211201_P01_WALL-PANEL-FRAME-BACK-LOWER-B1_CAD (Autodesk Fusion 360 design; units mm, degrees)
part number: 2026-11-01-01-29-27-664
description: WALL - PANEL FRAME - BACK LOWER - B1 | Vách hậu - khung dưới trái | P01
part number: 211201
Autodesk Fusion 360 part; units mm, degrees
ref_plane "WorkPlane1" through (0, 0, 112.26) normal (0, 0, 1) x (1, 0, 0) in component "211201 WALL - PANEL FRAME - BACK LOWER - B1"
sketch "SKETCH - RAIL - BOTTOM TUBE" plane through (0, 0, 112.26) normal (0, 0, 1) x (1, 0, 0) in component "211201 WALL - PANEL FRAME - BACK LOWER - B1"
  line L0 (-1201.74, 804) -> (-2.75, 804)
  line L1 (-2.75, 804) -> (-2.75, 844)
  line L2 (-2.75, 844) -> (-1201.74, 844)
  line L3 (-1201.74, 844) -> (-1201.74, 804)
  dimension "d507" = 1198.99
  dimension "d508" = 40
  dimension "d509" = 1201.74
  dimension "d510" = 804
  constraint horizontal L0
  constraint vertical L1
  constraint horizontal L2
  constraint vertical L3
  measures "d507" horizontal distance of L0.start L0.end
  measures "d508" vertical distance of L0.start L2.end
  measures "d509" horizontal distance of origin L0.start
  measures "d510" vertical distance of origin L0.start
extrude "EXTRUDE - RAIL - BOTTOM TUBE" add sketch "SKETCH - RAIL - BOTTOM TUBE" along normal blind 20 makes body 1 in component "211201 WALL - PANEL FRAME - BACK LOWER - B1"
ref_plane "WorkPlane2" through (0, 0, 113.46) normal (0, 0, 1) x (1, 0, 0) in component "211201 WALL - PANEL FRAME - BACK LOWER - B1"
sketch "SKETCH - RAIL - BOTTOM BORE" plane through (0, 0, 113.46) normal (0, 0, 1) x (1, 0, 0) in component "211201 WALL - PANEL FRAME - BACK LOWER - B1"
  line L0 (-1201.74, 805.2) -> (-2.75, 805.2)
  line L1 (-2.75, 805.2) -> (-2.75, 842.8)
  line L2 (-2.75, 842.8) -> (-1201.74, 842.8)
  line L3 (-1201.74, 842.8) -> (-1201.74, 805.2)
  dimension "d515" = 1198.99
  dimension "d516" = 37.6
  dimension "d517" = 1201.74
  dimension "d518" = 805.2
  constraint horizontal L0
  constraint vertical L1
  constraint horizontal L2
  constraint vertical L3
  measures "d515" horizontal distance of L0.start L0.end
  measures "d516" vertical distance of L0.start L2.end
  measures "d517" horizontal distance of origin L0.start
  measures "d518" vertical distance of origin L0.start
extrude "CUT - RAIL - BOTTOM BORE" cut sketch "SKETCH - RAIL - BOTTOM BORE" along normal blind 17.6 bodies 1 in component "211201 WALL - PANEL FRAME - BACK LOWER - B1"
ref_plane "WorkPlane3" through (0, 0, 1210.87) normal (0, 0, 1) x (1, 0, 0) in component "211201 WALL - PANEL FRAME - BACK LOWER - B1"
sketch "SKETCH - RAIL - TOP TUBE" plane through (0, 0, 1210.87) normal (0, 0, 1) x (1, 0, 0) in component "211201 WALL - PANEL FRAME - BACK LOWER - B1"
  line L0 (-1201.74, 804) -> (-2.75, 804)
  line L1 (-2.75, 804) -> (-2.75, 844)
  line L2 (-2.75, 844) -> (-1201.74, 844)
  line L3 (-1201.74, 844) -> (-1201.74, 804)
  dimension "d523" = 1198.99
  dimension "d524" = 40
  dimension "d525" = 1201.74
  dimension "d526" = 804
  constraint horizontal L0
  constraint vertical L1
  constraint horizontal L2
  constraint vertical L3
  measures "d523" horizontal distance of L0.start L0.end
  measures "d524" vertical distance of L0.start L2.end
  measures "d525" horizontal distance of origin L0.start
  measures "d526" vertical distance of origin L0.start
extrude "EXTRUDE - RAIL - TOP TUBE" add sketch "SKETCH - RAIL - TOP TUBE" along normal blind 20 separate body makes body 2 in component "211201 WALL - PANEL FRAME - BACK LOWER - B1"
ref_plane "WorkPlane4" through (0, 0, 1212.07) normal (0, 0, 1) x (1, 0, 0) in component "211201 WALL - PANEL FRAME - BACK LOWER - B1"
sketch "SKETCH - RAIL - TOP BORE" plane through (0, 0, 1212.07) normal (0, 0, 1) x (1, 0, 0) in component "211201 WALL - PANEL FRAME - BACK LOWER - B1"
  line L0 (-1201.74, 805.2) -> (-2.75, 805.2)
  line L1 (-2.75, 805.2) -> (-2.75, 842.8)
  line L2 (-2.75, 842.8) -> (-1201.74, 842.8)
  line L3 (-1201.74, 842.8) -> (-1201.74, 805.2)
  dimension "d531" = 1198.99
  dimension "d532" = 37.6
  dimension "d533" = 1201.74
  dimension "d534" = 805.2
  constraint horizontal L0
  constraint vertical L1
  constraint horizontal L2
  constraint vertical L3
  measures "d531" horizontal distance of L0.start L0.end
  measures "d532" vertical distance of L0.start L2.end
  measures "d533" horizontal distance of origin L0.start
  measures "d534" vertical distance of origin L0.start
extrude "CUT - RAIL - TOP BORE" cut sketch "SKETCH - RAIL - TOP BORE" along normal blind 17.6 bodies 2 in component "211201 WALL - PANEL FRAME - BACK LOWER - B1"
ref_plane "WorkPlane5" through (0, 0, 132.26) normal (0, 0, 1) x (1, 0, 0) in component "211201 WALL - PANEL FRAME - BACK LOWER - B1"
sketch "SKETCH - STILE - OUTER TUBE" plane through (0, 0, 132.26) normal (0, 0, 1) x (1, 0, 0) in component "211201 WALL - PANEL FRAME - BACK LOWER - B1"
  line L0 (-1201.74, 804) -> (-1181.74, 804)
  line L1 (-1181.74, 804) -> (-1181.74, 844)
  line L2 (-1181.74, 844) -> (-1201.74, 844)
  line L3 (-1201.74, 844) -> (-1201.74, 804)
  dimension "d539" = 20
  dimension "d540" = 40
  dimension "d541" = 1201.74
  dimension "d542" = 804
  constraint horizontal L0
  constraint vertical L1
  constraint horizontal L2
  constraint vertical L3
  measures "d539" horizontal distance of L0.start L0.end
  measures "d540" vertical distance of L0.start L2.end
  measures "d541" horizontal distance of origin L0.start
  measures "d542" vertical distance of origin L0.start
extrude "EXTRUDE - STILE - OUTER TUBE" add sketch "SKETCH - STILE - OUTER TUBE" along normal blind 1078.61 separate body makes body 3 in component "211201 WALL - PANEL FRAME - BACK LOWER - B1"
ref_plane "WorkPlane6" through (0, 0, 132.26) normal (0, 0, 1) x (1, 0, 0) in component "211201 WALL - PANEL FRAME - BACK LOWER - B1"
sketch "SKETCH - STILE - OUTER BORE" plane through (0, 0, 132.26) normal (0, 0, 1) x (1, 0, 0) in component "211201 WALL - PANEL FRAME - BACK LOWER - B1"
  line L0 (-1200.54, 805.2) -> (-1182.94, 805.2)
  line L1 (-1182.94, 805.2) -> (-1182.94, 842.8)
  line L2 (-1182.94, 842.8) -> (-1200.54, 842.8)
  line L3 (-1200.54, 842.8) -> (-1200.54, 805.2)
  dimension "d547" = 17.6
  dimension "d548" = 37.6
  dimension "d549" = 1200.54
  dimension "d550" = 805.2
  constraint horizontal L0
  constraint vertical L1
  constraint horizontal L2
  constraint vertical L3
  measures "d547" horizontal distance of L0.start L0.end
  measures "d548" vertical distance of L0.start L2.end
  measures "d549" horizontal distance of origin L0.start
  measures "d550" vertical distance of origin L0.start
extrude "CUT - STILE - OUTER BORE" cut sketch "SKETCH - STILE - OUTER BORE" along normal blind 1078.61 bodies 3 in component "211201 WALL - PANEL FRAME - BACK LOWER - B1"
ref_plane "WorkPlane7" through (0, 0, 132.26) normal (0, 0, 1) x (1, 0, 0) in component "211201 WALL - PANEL FRAME - BACK LOWER - B1"
sketch "SKETCH - STILE - CENTRE TUBE" plane through (0, 0, 132.26) normal (0, 0, 1) x (1, 0, 0) in component "211201 WALL - PANEL FRAME - BACK LOWER - B1"
  line L0 (-22.75, 804) -> (-2.75, 804)
  line L1 (-2.75, 804) -> (-2.75, 844)
  line L2 (-2.75, 844) -> (-22.75, 844)
  line L3 (-22.75, 844) -> (-22.75, 804)
  dimension "d555" = 20
  dimension "d556" = 40
  dimension "d557" = 22.75
  dimension "d558" = 804
  constraint horizontal L0
  constraint vertical L1
  constraint horizontal L2
  constraint vertical L3
  measures "d555" horizontal distance of L0.start L0.end
  measures "d556" vertical distance of L0.start L2.end
  measures "d557" horizontal distance of origin L0.start
  measures "d558" vertical distance of origin L0.start
extrude "EXTRUDE - STILE - CENTRE TUBE" add sketch "SKETCH - STILE - CENTRE TUBE" along normal blind 1078.61 separate body makes body 4 in component "211201 WALL - PANEL FRAME - BACK LOWER - B1"
ref_plane "WorkPlane8" through (0, 0, 132.26) normal (0, 0, 1) x (1, 0, 0) in component "211201 WALL - PANEL FRAME - BACK LOWER - B1"
sketch "SKETCH - STILE - CENTRE BORE" plane through (0, 0, 132.26) normal (0, 0, 1) x (1, 0, 0) in component "211201 WALL - PANEL FRAME - BACK LOWER - B1"
  line L0 (-21.55, 805.2) -> (-3.95, 805.2)
  line L1 (-3.95, 805.2) -> (-3.95, 842.8)
  line L2 (-3.95, 842.8) -> (-21.55, 842.8)
  line L3 (-21.55, 842.8) -> (-21.55, 805.2)
  dimension "d563" = 17.6
  dimension "d564" = 37.6
  dimension "d565" = 21.55
  dimension "d566" = 805.2
  constraint horizontal L0
  constraint vertical L1
  constraint horizontal L2
  constraint vertical L3
  measures "d563" horizontal distance of L0.start L0.end
  measures "d564" vertical distance of L0.start L2.end
  measures "d565" horizontal distance of origin L0.start
  measures "d566" vertical distance of origin L0.start
extrude "CUT - STILE - CENTRE BORE" cut sketch "SKETCH - STILE - CENTRE BORE" along normal blind 1078.61 bodies 4 in component "211201 WALL - PANEL FRAME - BACK LOWER - B1"
ref_plane "WorkPlane9" through (0, 0, 132.26) normal (0, 0, 1) x (1, 0, 0) in component "211201 WALL - PANEL FRAME - BACK LOWER - B1"
sketch "SKETCH - STILE - MID 1 TUBE" plane through (0, 0, 132.26) normal (0, 0, 1) x (1, 0, 0) in component "211201 WALL - PANEL FRAME - BACK LOWER - B1"
  line L0 (-808.7433, 804) -> (-788.7433, 804)
  line L1 (-788.7433, 804) -> (-788.7433, 844)
  line L2 (-788.7433, 844) -> (-808.7433, 844)
  line L3 (-808.7433, 844) -> (-808.7433, 804)
  dimension "d571" = 20
  dimension "d572" = 40
  dimension "d573" = 808.7433
  dimension "d574" = 804
  constraint horizontal L0
  constraint vertical L1
  constraint horizontal L2
  constraint vertical L3
  measures "d571" horizontal distance of L0.start L0.end
  measures "d572" vertical distance of L0.start L2.end
  measures "d573" horizontal distance of origin L0.start
  measures "d574" vertical distance of origin L0.start
extrude "EXTRUDE - STILE - MID 1 TUBE" add sketch "SKETCH - STILE - MID 1 TUBE" along normal blind 1078.61 separate body makes body 5 in component "211201 WALL - PANEL FRAME - BACK LOWER - B1"
ref_plane "WorkPlane10" through (0, 0, 132.26) normal (0, 0, 1) x (1, 0, 0) in component "211201 WALL - PANEL FRAME - BACK LOWER - B1"
sketch "SKETCH - STILE - MID 1 BORE" plane through (0, 0, 132.26) normal (0, 0, 1) x (1, 0, 0) in component "211201 WALL - PANEL FRAME - BACK LOWER - B1"
  line L0 (-807.7433, 805) -> (-789.7433, 805)
  line L1 (-789.7433, 805) -> (-789.7433, 843)
  line L2 (-789.7433, 843) -> (-807.7433, 843)
  line L3 (-807.7433, 843) -> (-807.7433, 805)
  dimension "d579" = 18
  dimension "d580" = 38
  dimension "d581" = 807.7433
  dimension "d582" = 805
  constraint horizontal L0
  constraint vertical L1
  constraint horizontal L2
  constraint vertical L3
  measures "d579" horizontal distance of L0.start L0.end
  measures "d580" vertical distance of L0.start L2.end
  measures "d581" horizontal distance of origin L0.start
  measures "d582" vertical distance of origin L0.start
extrude "CUT - STILE - MID 1 BORE" cut sketch "SKETCH - STILE - MID 1 BORE" along normal blind 1078.61 bodies 5 in component "211201 WALL - PANEL FRAME - BACK LOWER - B1"
pattern_linear "PATTERN - STILES - MID" count 2 spacing 392.9967 along (1, 0, 0) of bodies 5 makes body 6 in component "211201 WALL - PANEL FRAME - BACK LOWER - B1"
ref_plane "WorkPlane11" through (0, 0, 112.26) normal (0, 0, 1) x (1, 0, 0) in component "211201 WALL - PANEL FRAME - BACK LOWER - B1"
sketch "HOLE CENTRE - BOTTOM RAIL BOLT CLEARANCE 1" plane through (0, 0, 112.26) normal (0, 0, 1) x (1, 0, 0) in component "211201 WALL - PANEL FRAME - BACK LOWER - B1"
  point P0 (-981.74, 824)
  dimension "d591" = 981.74
  dimension "d592" = 824
  measures "d591" horizontal distance of origin P0
  measures "d592" vertical distance of origin P0
hole "HOLE - BOTTOM RAIL BOLT CLEARANCE 1" at (-981.74, 824, 112.26) direction (0, 0, 1) diameter 7 depth 1.2 tip angle 118 bodies 1 in component "211201 WALL - PANEL FRAME - BACK LOWER - B1"
ref_plane "WorkPlane12" through (0, 0, 132.26) normal (0, 0, 1) x (1, 0, 0) in component "211201 WALL - PANEL FRAME - BACK LOWER - B1"
sketch "HOLE CENTRE - BOTTOM RAIL KEY ACCESS 1" plane through (0, 0, 132.26) normal (0, 0, 1) x (1, 0, 0) in component "211201 WALL - PANEL FRAME - BACK LOWER - B1"
  point P0 (-981.74, 824)
  dimension "d598" = 981.74
  dimension "d599" = 824
  measures "d598" horizontal distance of origin P0
  measures "d599" vertical distance of origin P0
hole "HOLE - BOTTOM RAIL KEY ACCESS 1" at (-981.74, 824, 132.26) direction (0, 0, -1) diameter 19 depth 1.2 tip angle 118 bodies 1 in component "211201 WALL - PANEL FRAME - BACK LOWER - B1"
pattern_linear "PATTERN - BOTTOM RAIL BOLT HOLES" count 4 spacing 252.9967 along (1, 0, 0) of "HOLE - BOTTOM RAIL BOLT CLEARANCE 1", "HOLE - BOTTOM RAIL KEY ACCESS 1" in component "211201 WALL - PANEL FRAME - BACK LOWER - B1"
ref_plane "WorkPlane13" through (0, 0, 112.26) normal (0, 0, 1) x (1, 0, 0) in component "211201 WALL - PANEL FRAME - BACK LOWER - B1"
sketch "HOLE CENTRE - BOTTOM RAIL SPIGOT ROUND" plane through (0, 0, 112.26) normal (0, 0, 1) x (1, 0, 0) in component "211201 WALL - PANEL FRAME - BACK LOWER - B1"
  point P0 (-102.75, 824)
  dimension "d609" = 102.75
  dimension "d610" = 824
  measures "d609" horizontal distance of origin P0
  measures "d610" vertical distance of origin P0
hole "HOLE - BOTTOM RAIL SPIGOT ROUND" at (-102.75, 824, 112.26) direction (0, 0, 1) diameter 8.5 depth 1.2 tip angle 118 bodies 1 in component "211201 WALL - PANEL FRAME - BACK LOWER - B1"
ref_plane "WorkPlane14" through (0, 0, 112.26) normal (0, 0, 1) x (1, 0, 0) in component "211201 WALL - PANEL FRAME - BACK LOWER - B1"
sketch "SKETCH - BOTTOM RAIL SPIGOT SLOT" plane through (0, 0, 112.26) normal (0, 0, 1) x (1, 0, 0) in component "211201 WALL - PANEL FRAME - BACK LOWER - B1"
  line L0 (-1104.49, 819.75) -> (-1098.99, 819.75)
  line L1 (-1098.99, 819.75) -> (-1098.99, 828.25)
  line L2 (-1098.99, 828.25) -> (-1104.49, 828.25)
  line L3 (-1104.49, 828.25) -> (-1104.49, 819.75)
  dimension "d616" = 5.5
  dimension "d617" = 8.5
  dimension "d618" = 1104.49
  dimension "d619" = 819.75
  constraint horizontal L0
  constraint vertical L1
  constraint horizontal L2
  constraint vertical L3
  measures "d616" horizontal distance of L0.start L0.end
  measures "d617" vertical distance of L0.start L2.end
  measures "d618" horizontal distance of origin L0.start
  measures "d619" vertical distance of origin L0.start
extrude "CUT - BOTTOM RAIL SPIGOT SLOT" cut sketch "SKETCH - BOTTOM RAIL SPIGOT SLOT" along normal blind 1.2 bodies 1 in component "211201 WALL - PANEL FRAME - BACK LOWER - B1"
ref_plane "WorkPlane15" through (0, 0, 112.26) normal (0, 0, 1) x (1, 0, 0) in component "211201 WALL - PANEL FRAME - BACK LOWER - B1"
sketch "HOLE CENTRE - BOTTOM RAIL SPIGOT SLOT END 1" plane through (0, 0, 112.26) normal (0, 0, 1) x (1, 0, 0) in component "211201 WALL - PANEL FRAME - BACK LOWER - B1"
  point P0 (-1104.49, 824)
  dimension "d624" = 1104.49
  dimension "d625" = 824
  measures "d624" horizontal distance of origin P0
  measures "d625" vertical distance of origin P0
hole "HOLE - BOTTOM RAIL SPIGOT SLOT END 1" at (-1104.49, 824, 112.26) direction (0, 0, 1) diameter 8.5 depth 1.2 tip angle 118 bodies 1 in component "211201 WALL - PANEL FRAME - BACK LOWER - B1"
ref_plane "WorkPlane16" through (0, 0, 112.26) normal (0, 0, 1) x (1, 0, 0) in component "211201 WALL - PANEL FRAME - BACK LOWER - B1"
sketch "HOLE CENTRE - BOTTOM RAIL SPIGOT SLOT END 2" plane through (0, 0, 112.26) normal (0, 0, 1) x (1, 0, 0) in component "211201 WALL - PANEL FRAME - BACK LOWER - B1"
  point P0 (-1098.99, 824)
  dimension "d631" = 1098.99
  dimension "d632" = 824
  measures "d631" horizontal distance of origin P0
  measures "d632" vertical distance of origin P0
hole "HOLE - BOTTOM RAIL SPIGOT SLOT END 2" at (-1098.99, 824, 112.26) direction (0, 0, 1) diameter 8.5 depth 1.2 tip angle 118 bodies 1 in component "211201 WALL - PANEL FRAME - BACK LOWER - B1"
ref_plane "WorkPlane17" through (0, 0, 1230.87) normal (0, 0, 1) x (1, 0, 0) in component "211201 WALL - PANEL FRAME - BACK LOWER - B1"
sketch "HOLE CENTRE - TOP RAIL RIVNUT 1" plane through (0, 0, 1230.87) normal (0, 0, 1) x (1, 0, 0) in component "211201 WALL - PANEL FRAME - BACK LOWER - B1"
  point P0 (-981.74, 824)
  dimension "d638" = 981.74
  dimension "d639" = 824
  measures "d638" horizontal distance of origin P0
  measures "d639" vertical distance of origin P0
hole "HOLE - TOP RAIL RIVNUT 1" at (-981.74, 824, 1230.87) direction (0, 0, -1) diameter 9.53 depth 1.2 tip angle 118 bodies 2 in component "211201 WALL - PANEL FRAME - BACK LOWER - B1"
pattern_linear "PATTERN - TOP RAIL RIVNUTS" count 4 spacing 252.9967 along (1, 0, 0) of "HOLE - TOP RAIL RIVNUT 1" in component "211201 WALL - PANEL FRAME - BACK LOWER - B1"
ref_plane "WorkPlane18" through (0, 0, 1230.87) normal (0, 0, 1) x (1, 0, 0) in component "211201 WALL - PANEL FRAME - BACK LOWER - B1"
sketch "HOLE CENTRE - TOP RAIL SPIGOT RIVNUT LOW X" plane through (0, 0, 1230.87) normal (0, 0, 1) x (1, 0, 0) in component "211201 WALL - PANEL FRAME - BACK LOWER - B1"
  point P0 (-1101.74, 824)
  dimension "d649" = 1101.74
  dimension "d650" = 824
  measures "d649" horizontal distance of origin P0
  measures "d650" vertical distance of origin P0
hole "HOLE - TOP RAIL SPIGOT RIVNUT LOW X" at (-1101.74, 824, 1230.87) direction (0, 0, -1) diameter 9.53 depth 1.2 tip angle 118 bodies 2 in component "211201 WALL - PANEL FRAME - BACK LOWER - B1"
ref_plane "WorkPlane19" through (0, 0, 1230.87) normal (0, 0, 1) x (1, 0, 0) in component "211201 WALL - PANEL FRAME - BACK LOWER - B1"
sketch "HOLE CENTRE - TOP RAIL SPIGOT RIVNUT HIGH X" plane through (0, 0, 1230.87) normal (0, 0, 1) x (1, 0, 0) in component "211201 WALL - PANEL FRAME - BACK LOWER - B1"
  point P0 (-102.75, 824)
  dimension "d656" = 102.75
  dimension "d657" = 824
  measures "d656" horizontal distance of origin P0
  measures "d657" vertical distance of origin P0
hole "HOLE - TOP RAIL SPIGOT RIVNUT HIGH X" at (-102.75, 824, 1230.87) direction (0, 0, -1) diameter 9.53 depth 1.2 tip angle 118 bodies 2 in component "211201 WALL - PANEL FRAME - BACK LOWER - B1"
ref_plane "WorkPlane20" through (-1201.74, 0, 0) normal (1, 0, 0) x (0, 1, 0) in component "211201 WALL - PANEL FRAME - BACK LOWER - B1"
sketch "HOLE CENTRE - OUTER STILE CORNER BOLT CLEARANCE 1" plane through (-1201.74, 0, 0) normal (1, 0, 0) x (0, 0, -1) in component "211201 WALL - PANEL FRAME - BACK LOWER - B1"
  point P0 (-332.26, 824)
  dimension "d663" = 824
  dimension "d664" = 332.26
  measures "d663" vertical distance of origin P0
  measures "d664" horizontal distance of origin P0
hole "HOLE - OUTER STILE CORNER BOLT CLEARANCE 1" at (-1201.74, 824, 332.26) direction (1, 0, 0) diameter 7 depth 1.2 tip angle 118 bodies 3 in component "211201 WALL - PANEL FRAME - BACK LOWER - B1"
ref_plane "WorkPlane21" through (-1181.74, 0, 0) normal (1, 0, 0) x (0, 1, 0) in component "211201 WALL - PANEL FRAME - BACK LOWER - B1"
sketch "HOLE CENTRE - OUTER STILE CORNER KEY ACCESS 1" plane through (-1181.74, 0, 0) normal (1, 0, 0) x (0, 0, -1) in component "211201 WALL - PANEL FRAME - BACK LOWER - B1"
  point P0 (-332.26, 824)
  dimension "d670" = 824
  dimension "d671" = 332.26
  measures "d670" vertical distance of origin P0
  measures "d671" horizontal distance of origin P0
hole "HOLE - OUTER STILE CORNER KEY ACCESS 1" at (-1181.74, 824, 332.26) direction (-1, 0, 0) diameter 19 depth 1.2 tip angle 118 bodies 3 in component "211201 WALL - PANEL FRAME - BACK LOWER - B1"
pattern_linear "PATTERN - OUTER STILE CORNER BOLT HOLES" count 3 spacing 339.305 along (0, 0, 1) of "HOLE - OUTER STILE CORNER BOLT CLEARANCE 1", "HOLE - OUTER STILE CORNER KEY ACCESS 1" in component "211201 WALL - PANEL FRAME - BACK LOWER - B1"
ref_plane "WorkPlane22" through (-2.75, 0, 0) normal (1, 0, 0) x (0, 1, 0) in component "211201 WALL - PANEL FRAME - BACK LOWER - B1"
sketch "HOLE CENTRE - CENTRE STILE PIN HOLE 1" plane through (-2.75, 0, 0) normal (1, 0, 0) x (0, 0, -1) in component "211201 WALL - PANEL FRAME - BACK LOWER - B1"
  point P0 (-332.26, 824)
  dimension "d681" = 824
  dimension "d682" = 332.26
  measures "d681" vertical distance of origin P0
  measures "d682" horizontal distance of origin P0
hole "HOLE - CENTRE STILE PIN HOLE 1" at (-2.75, 824, 332.26) direction (-1, 0, 0) diameter 7 depth 1.2 tip angle 118 bodies 4 in component "211201 WALL - PANEL FRAME - BACK LOWER - B1"
pattern_linear "PATTERN - CENTRE STILE PIN HOLES" count 3 spacing 339.305 along (0, 0, 1) of "HOLE - CENTRE STILE PIN HOLE 1" in component "211201 WALL - PANEL FRAME - BACK LOWER - B1"
chamfer "CHAMFER - CLOSING SEAM LEAD-IN (R-J9)" distance 1 angle 45 1 edges at (-2.75, 824, 1230.87) tangent chain off on bodies 2 in component "211201 WALL - PANEL FRAME - BACK LOWER - B1"
component "211201 WALL - PANEL FRAME - BACK LOWER - B1" placed x (1, 0, 0) y (0, 1, 0) z (0, 0, 1) at (0, 0, 0)
equation "pod_w_Ref = 2500 mm" comment "DECIDED: D-01; conventions s4 (X = +-1250)"
equation "pod_d_Ref = 1700 mm" comment "DECIDED: D-01; conventions s4 (Y = +-850)"
equation "pod_h_Ref = 2400 mm" comment "DECIDED: D-21 (room floor to roof skin top)"
equation "glide_h_Ref = 10 mm" comment "ASSUMPTION: layout study inputs.py glide_h"
equation "band_h_Ref = 100 mm" comment "SOURCE: layout study B1 list B-BAND 100x40; inputs.py base_h"
equation "outer_t_Ref = skin_t_Ref + bond_t_Ref + frame_t_Ref" comment "DECIDED: PM ruling 2026-10-31: ACP 3 + bond line 3 + frame 40, walls and ceiling (was 43)"
equation "cav_gap_Ref = 4 mm" comment "DECIDED: D-16, D-42: the gap between the outer panel and the lining cassette in the wall and ceiling stack"
equation "cass_t_Ref = 34 mm" comment "SOURCE: layout study B1 final list L-CASS 34 (tray + 25 gap + felt 9)"
equation "stack_t_Ref = outer_t_Ref + cav_gap_Ref + cass_t_Ref" comment "CALCULATION: D-16, D-42 stack, walls and ceiling: outer panel + cavity gap + cassette (PM ruling 2026-10-31 on outer_t)"
equation "lin_gap_Ref = 4 mm" comment "ASSUMPTION: PM ruling pass C: gap above the upper side linings so they stay floating (= the 4 mm stack gap)"
equation "seam_gap_Ref = 2.26 mm" comment "DECIDED: PM ruling 2026-10-31 (Mechanical Checker F-001, F-005): the Joints Engineer's 2.26 mm at all nine site seam types, set by a metal stop (1.5 stop washer + 0.76 rivnut head; joints register section 2.8)"
equation "wall_z0_Ref = glide_h_Ref + band_h_Ref" comment "CALCULATION: base band top: glides + band"
equation "panel_z0_Ref = wall_z0_Ref + seam_gap_Ref" comment "CALCULATION: walls stand one seam_gap above the band top (joints register 2.8, IF-01)"
equation "back_oh_Ref = pod_h_Ref - outer_t_Ref - seam_gap_Ref - panel_z0_Ref" comment "CALCULATION: PM ruling 2026-10-31 (pass D, F-004): the back outer frames run up to the ceiling frame (pod_h - outer_t), less the seam_gap under it, closing the slot at the back top edge"
equation "back_ph_Ref = ( back_oh_Ref - seam_gap_Ref ) / 2" comment "CALCULATION: D-23: 4 sheets on the back, two equal rows with one seam_gap between them (joints register 2.8); the lower back linings match the lower row, as on the side walls"
equation "half_pw_Ref = ( pod_w_Ref - 2 * outer_t_Ref - 3 * seam_gap_Ref ) / 2" comment "CALCULATION: SKIN width of each back and ceiling panel: two skins and three seam_gap seams between the side frames (F-001, joints register 2.8)"
equation "n_base_bolt_Ref = 4" comment "DECIDED: PM ruling 2026-10-31, J-BASE-01: bolts per panel along the band, evenly spaced"
equation "skin_t_Ref = 3 mm" comment "DECIDED: ACP skin, walls and ceiling (D-16; PM ruling 2026-10-31 on outer_t)"
equation "bond_t_Ref = 3 mm" comment "DECIDED: bond line between the ACP and the frame (PM ruling 2026-10-31 on outer_t)"
equation "frame_t_Ref = 40 mm" comment "DECIDED: aluminium frame tube depth, walls and ceiling (PM ruling 2026-10-31 on outer_t)"
equation "close_gap_Ref = 5.5 mm" comment "DECIDED: PM ruling 2026-10-31 (joints register, F-011/F-012): frame gap at the closing seams B1-B2, B3-B4 and C1-C2, which have no hard stop (slotted holes, thicker gasket)"
equation "half_fw_Ref = ( pod_w_Ref - 2 * outer_t_Ref - 2 * seam_gap_Ref - close_gap_Ref ) / 2" comment "CALCULATION: FRAME width of each back and ceiling panel: the skins overhang their frames by half_pw - half_fw at the closing seam (PM ruling 2026-10-31)"
equation "bolt_edge_inset_Ref = 220 mm" comment "DECIDED: PM ruling 2026-10-31: on every bolted edge the end bolts sit this far in from each panel end (the FRAME end, where the bolts go), the rest evenly spaced"
equation "spigot_inset_Ref = 100 mm" comment "DECIDED: PM ruling 2026-10-31: locating spigots this far in from each panel end (round hole at one end, slot at the other)"
equation "pod_w = pod_w_Ref" comment "LINKED: pod_w_Ref, derived from 100000_P04_POD-SKELETON_CAD v4 (skeleton is the single source)"
equation "pod_d = pod_d_Ref" comment "LINKED: pod_d_Ref, derived from 100000_P04_POD-SKELETON_CAD v4 (skeleton is the single source)"
equation "pod_h = pod_h_Ref" comment "LINKED: pod_h_Ref, derived from 100000_P04_POD-SKELETON_CAD v4 (skeleton is the single source)"
equation "panel_z0 = panel_z0_Ref" comment "LINKED: panel_z0_Ref, derived from 100000_P04_POD-SKELETON_CAD v4 (skeleton is the single source)"
equation "back_ph = back_ph_Ref" comment "LINKED: back_ph_Ref, derived from 100000_P04_POD-SKELETON_CAD v4 (skeleton is the single source)"
equation "back_oh = back_oh_Ref" comment "LINKED: back_oh_Ref, derived from 100000_P04_POD-SKELETON_CAD v4 (skeleton is the single source)"
equation "half_pw = half_pw_Ref" comment "LINKED: half_pw_Ref, derived from 100000_P04_POD-SKELETON_CAD v4 (skeleton is the single source)"
equation "half_fw = half_fw_Ref" comment "LINKED: half_fw_Ref, derived from 100000_P04_POD-SKELETON_CAD v4 (skeleton is the single source)"
equation "close_gap = close_gap_Ref" comment "LINKED: close_gap_Ref, derived from 100000_P04_POD-SKELETON_CAD v4 (skeleton is the single source)"
equation "stack_t = stack_t_Ref" comment "LINKED: stack_t_Ref, derived from 100000_P04_POD-SKELETON_CAD v4 (skeleton is the single source)"
equation "outer_t = outer_t_Ref" comment "LINKED: outer_t_Ref, derived from 100000_P04_POD-SKELETON_CAD v4 (skeleton is the single source)"
equation "cass_t = cass_t_Ref" comment "LINKED: cass_t_Ref, derived from 100000_P04_POD-SKELETON_CAD v4 (skeleton is the single source)"
equation "lin_gap = lin_gap_Ref" comment "LINKED: lin_gap_Ref, derived from 100000_P04_POD-SKELETON_CAD v4 (skeleton is the single source)"
equation "seam_gap = seam_gap_Ref" comment "LINKED: seam_gap_Ref, derived from 100000_P04_POD-SKELETON_CAD v4 (skeleton is the single source)"
equation "skin_t = skin_t_Ref" comment "LINKED: skin_t_Ref, derived from 100000_P04_POD-SKELETON_CAD v4 (skeleton is the single source)"
equation "bond_t = bond_t_Ref" comment "LINKED: bond_t_Ref, derived from 100000_P04_POD-SKELETON_CAD v4 (skeleton is the single source)"
equation "bolt_edge_inset = bolt_edge_inset_Ref" comment "LINKED: bolt_edge_inset_Ref, derived from 100000_P04_POD-SKELETON_CAD v4 (skeleton is the single source)"
equation "spigot_inset = spigot_inset_Ref" comment "LINKED: spigot_inset_Ref, derived from 100000_P04_POD-SKELETON_CAD v4 (skeleton is the single source)"
equation "n_base_bolt = n_base_bolt_Ref" comment "LINKED: n_base_bolt_Ref, derived from 100000_P04_POD-SKELETON_CAD v4 (skeleton is the single source)"
equation "tube_w = 20 mm" comment "CONFIRMED: D-34, D-54: aluminium tube 20 x 40 x 1.2; the 20 mm face carries the skin, so the 40 mm runs through the wall (outer_t = ACP 3 + frame 40). The joint register may turn it for the bond width (HOLD)"
equation "tube_d = outer_t - skin_t - bond_t" comment "CALCULATION: frame depth = outer panel 46 - skin 3 - bond 3 = 40 (D-34)"
equation "tube_t = 1.2 mm" comment "CONFIRMED: D-34, D-54, D-85: perimeter members (rails, front and back stiles) keep the 1.2 mm wall; they carry the rivnuts (grip check passed)"
equation "stud_t = 1.0 mm" comment "CONFIRMED: D-85 (weight): intermediate studs at a 1.0 mm wall; they carry no rivnut, only the skin's bond line"
equation "stile_pitch_max = 400 mm" comment "CONFIRMED: D-16, D-34: members 400 mm apart or less, to keep the ACP flat"
equation "skin_setback = 0 mm" comment "ASSUMPTION: skin edge set back from the frame's top and bottom edges: 0, so the outside reveal equals the 2.26 seam gap (D-23: crisp, aligned reveals; joints register 2.8 leaves the setback to the WALL drawing)"
equation "fill_t = tube_d" comment "CALCULATION: 40 mm PET fill fills the frame depth (D-34; layout study 40 mm)"
equation "bolt_d = 7 mm" comment "CONFIRMED: PM ruling on F-009: bolt holes 7.0 (0.51 float), position tolerance 0.4 (+-0.2) from the spigot hole, CNC or drill jig (joints register FR-02)"
equation "access_d = 19 mm" comment "CALCULATION: register FR-03: passes the 18 mm head washer (ISO 7093-1, R-J10), the M6 head and the 5 mm key; holds the grommet retainer (H-02)"
equation "bolt_line_y = pod_d / 2 - skin_t - bond_t - tube_d / 2" comment "CONFIRMED: J-WALL-02 bolt line on the back panel's tube centre, Y 824 (joints register R-J15, FR-07)"
equation "rivnut_d = 9.53 mm" comment "SOURCE: Sherex CAH3-610-4.2 hole 9.53 +0.10 (HW-SEL A5; register H-03)"
equation "spigot_d = 8.5 mm" comment "ASSUMPTION: register FR-05: hole for the 8 mm locating spigot H-05"
equation "spigot_slot = 14 mm" comment "ASSUMPTION: register FR-05: slot length for the second spigot"
equation "spigot_edge = spigot_inset" comment "CALCULATION: the skeleton's spigot_inset: spigots 100 from each end of the edge (PM ruling 2026-10-31, R-J13)"
equation "bolt_edge = bolt_edge_inset" comment "CALCULATION: the skeleton's bolt_edge_inset: end bolts 220 in from the panel's ends, evenly spaced, every bolt 30 or more from any stile (PM ruling 2026-10-31, R-J14)"
equation "pocket_w = 60 mm" comment "ASSUMPTION: register FR-10: fill left out 60 x 60 next to each bolt for the key"
equation "felt_t = 9 mm" comment "SOURCE: plan VT03-PET 9 mm PET felt; HW-SEL A3; D-31 (the factory's felt)"
equation "tray_t = 0.5 mm" comment "CONFIRMED: D-37: galvanised steel tray 0.5 mm"
equation "tray_h = cass_t" comment "CONFIRMED: PM ruling 2026-10-31 (WALL group, option 1): the wall cassettes use the ceiling's tray, returns the full cassette depth (34) turned in as lips that hold the felt, no ribs; settles H09 for the walls"
equation "lip_w = 12 mm" comment "CONFIRMED: PM ruling 2026-10-31 (WALL group, option 1): 12 mm lips hold the felt edge"
equation "bend_r = tray_t" comment "ASSUMPTION: inside bend radius 1 x t for 0.5 mm DX51D (the sheet metal rule's bend radius is its Thickness); the factory's tooling sets it (guideline 9)"
equation "felt_c = 1 mm" comment "ASSUMPTION: felt edge clearance inside the returns, as the ceiling cassette"
equation "gap_h = tray_h - felt_t - 2 * tray_t" comment "CALCULATION: air gap between the tray base and the felt (24): the acoustic gap (D-17) and the cable path (D-26)"
equation "clip_zone_h = 60 mm" comment "ASSUMPTION: height of each reserved clip zone (H03: no clip named)"
equation "clip_zone_dz = 100 mm" comment "ASSUMPTION: clip zone centre from the cassette's top and bottom edges (H03)"
equation "stopw_od = 20 mm" comment "SOURCE: joints register H-08: stop washer Ø10.5 x Ø20 x 1.5 (PROPOSED part)"
equation "stopw_id = 10.5 mm" comment "SOURCE: joints register H-08"
equation "stopw_t = 1.5 mm" comment "SOURCE: joints register H-08: rivnut head 0.76 + washer 1.5 = the 2.26 stop (R-J5)"
equation "rivnut_head_d = 12.96 mm" comment "SOURCE: Sherex CAH3-610-4.2 head Ø12.96 (joints register H-03, SHX)"
equation "rivnut_head_t = 0.76 mm" comment "SOURCE: Sherex CAH3-610-4.2 head 0.76 ±0.08 (H-03, SHX)"
equation "rivnut_body_d = 9.5 mm" comment "SOURCE: Sherex CAH3-610-4.2 body Ø9.50 max (H-03, SHX)"
equation "rivnut_len = 10.16 mm" comment "SOURCE: Sherex CAH3-610-4.2 installed length 10.16 max under the head (H-03, SHX); the bulge inside the tube is not modelled"
equation "m6_d = 6 mm" comment "CALCULATION: M6 threads shown at their 6 mm major diameter (no modelled thread)"
equation "spigot_pin_d = 8 mm" comment "SOURCE: joints register H-05: Ø8 stainless pin (PROPOSED, assumption sizes)"
equation "spigot_proud = 8 mm" comment "SOURCE: joints register H-05: stands 8 proud (read as: of the joint face)"
equation "spigot_thread_l = 10 mm" comment "ASSUMPTION: M6 thread into the spigot rivnut; H-05 gives no length; 10 stays inside the rivnut's 10.16"
equation "lead_in = 1 mm" comment "SOURCE: joints register 2.10 (R-J9): 1 x 45 degree lead-in on the top edge of each closing-seam face, so the panel beside it drops in past it without catching the bulb seal"
equation "pnl_len = half_pw" comment "CALCULATION: skeleton half_pw: the back panel's skin width (1200.61 on P04)"
equation "frm_len = half_fw" comment "CALCULATION: the skeleton's half_fw, 1198.99: the frame stops close_gap / 2 from X 0 and 1.62 short of its skin (R-J16)"
equation "pnl_h = back_ph" comment "CALCULATION: skeleton back row height (1118.61 on P04)"
equation "frm_h = pnl_h" comment "CALCULATION: the frame fills the row height; the seam gaps are outside it (P04)"
equation "top_h = tube_w" comment "CALCULATION: the back panels' top rails stay 20 x 40 (the ceiling's back member is the 40 x 40, R-J3)"
equation "stile_n_mid = ceil(( frm_len - tube_w ) / stile_pitch_max) - 1" comment "CALCULATION: intermediate stiles so that no stile pitch exceeds stile_pitch_max"
equation "stile_pitch = ( frm_len - tube_w ) / ( stile_n_mid + 1 )" comment "CALCULATION: equal stile pitch, centre to centre"
equation "stile_len = frm_h - 2 * tube_w" comment "CALCULATION: stiles between the full-width rails (butt joints)"
equation "n_len_bolt = n_base_bolt" comment "CALCULATION: the skeleton's n_base_bolt (4): also on the horizontal seam and the ceiling back edge (register 2.9; the skeleton's n_ceil_back_bolt 3 is an old assumption, flagged)"
equation "len_bolt_pitch = ( frm_len - 2 * bolt_edge ) / ( n_len_bolt - 1 )" comment "CALCULATION: 253.00 on P04: 220, 473.00, 725.99, 978.99 from the frame's ends (register 2.9; the skeleton's back_base_pitch uses the 1200.61 skin and gives 253.54, flagged to its owner)"
equation "n_side_jnt = 3" comment "SOURCE: 3 bolts on the back corner and on the closing seam (register 2.9)"
equation "side_jnt_pitch = ( pnl_h - 2 * bolt_edge ) / ( n_side_jnt - 1 )" comment "CALCULATION: 339.31 on P04: 220, 559.31, 898.61 up the 1118.61 edge (register 2.9)"
equation "cass_len = pod_w / 2 - stack_t - seam_gap / 2" comment "ASSUMPTION: PROPOSED (WALL): from the side lining's face to seam_gap / 2 short of X 0. Each cassette hangs on its own panel's frame and the closing seam moves (5.2 to 5.8, register 2.11), so the skeleton's touching edges at X 0 could clash; a 2.26 gap matches the skin seam above it (R-J16) and takes the H-14 edge seal"
equation "cass_h = pnl_h" comment "CALCULATION: lower: the row height; upper: up to lin_gap under the ceiling frame, floating (D-57; P04)"
equation "d505 = panel_z0"
equation "d507 = ( -close_gap / 2 ) - ( -close_gap / 2 - half_fw )"
equation "d508 = ( pod_d / 2 - skin_t - bond_t ) - ( pod_d / 2 - outer_t )"
equation "d509 = abs(-close_gap / 2 - half_fw)"
equation "d510 = abs(pod_d / 2 - outer_t)"
equation "d511 = ( ( panel_z0 ) + tube_w ) - ( panel_z0 )"
equation "d513 = ( panel_z0 ) + tube_t"
equation "d515 = ( -close_gap / 2 ) - ( -close_gap / 2 - half_fw )"
equation "d516 = ( ( pod_d / 2 - skin_t - bond_t ) - tube_t ) - ( ( pod_d / 2 - outer_t ) + tube_t )"
equation "d517 = abs(-close_gap / 2 - half_fw)"
equation "d518 = abs(( pod_d / 2 - outer_t ) + tube_t)"
equation "d519 = ( ( ( panel_z0 ) + tube_w ) - tube_t ) - ( ( panel_z0 ) + tube_t )"
equation "d521 = ( panel_z0 + back_ph ) - top_h"
equation "d523 = ( -close_gap / 2 ) - ( -close_gap / 2 - half_fw )"
equation "d524 = ( pod_d / 2 - skin_t - bond_t ) - ( pod_d / 2 - outer_t )"
equation "d525 = abs(-close_gap / 2 - half_fw)"
equation "d526 = abs(pod_d / 2 - outer_t)"
equation "d527 = ( panel_z0 + back_ph ) - ( ( panel_z0 + back_ph ) - top_h )"
equation "d529 = ( ( panel_z0 + back_ph ) - top_h ) + tube_t"
equation "d531 = ( -close_gap / 2 ) - ( -close_gap / 2 - half_fw )"
equation "d532 = ( ( pod_d / 2 - skin_t - bond_t ) - tube_t ) - ( ( pod_d / 2 - outer_t ) + tube_t )"
equation "d533 = abs(-close_gap / 2 - half_fw)"
equation "d534 = abs(( pod_d / 2 - outer_t ) + tube_t)"
equation "d535 = ( ( panel_z0 + back_ph ) - tube_t ) - ( ( ( panel_z0 + back_ph ) - top_h ) + tube_t )"
equation "d537 = ( panel_z0 ) + tube_w"
equation "d539 = ( ( -close_gap / 2 - half_fw ) + tube_w ) - ( -close_gap / 2 - half_fw )"
equation "d540 = ( pod_d / 2 - skin_t - bond_t ) - ( pod_d / 2 - outer_t )"
equation "d541 = abs(-close_gap / 2 - half_fw)"
equation "d542 = abs(pod_d / 2 - outer_t)"
equation "d543 = ( ( panel_z0 + back_ph ) - top_h ) - ( ( panel_z0 ) + tube_w )"
equation "d545 = ( panel_z0 ) + tube_w"
equation "d547 = ( ( ( -close_gap / 2 - half_fw ) + tube_w ) - tube_t ) - ( ( -close_gap / 2 - half_fw ) + tube_t )"
equation "d548 = ( ( pod_d / 2 - skin_t - bond_t ) - tube_t ) - ( ( pod_d / 2 - outer_t ) + tube_t )"
equation "d549 = abs(( -close_gap / 2 - half_fw ) + tube_t)"
equation "d550 = abs(( pod_d / 2 - outer_t ) + tube_t)"
equation "d551 = ( ( panel_z0 + back_ph ) - top_h ) - ( ( panel_z0 ) + tube_w )"
equation "d553 = ( panel_z0 ) + tube_w"
equation "d555 = ( -close_gap / 2 ) - ( ( -close_gap / 2 ) - tube_w )"
equation "d556 = ( pod_d / 2 - skin_t - bond_t ) - ( pod_d / 2 - outer_t )"
equation "d557 = abs(( -close_gap / 2 ) - tube_w)"
equation "d558 = abs(pod_d / 2 - outer_t)"
equation "d559 = ( ( panel_z0 + back_ph ) - top_h ) - ( ( panel_z0 ) + tube_w )"
equation "d561 = ( panel_z0 ) + tube_w"
equation "d563 = ( ( -close_gap / 2 ) - tube_t ) - ( ( ( -close_gap / 2 ) - tube_w ) + tube_t )"
equation "d564 = ( ( pod_d / 2 - skin_t - bond_t ) - tube_t ) - ( ( pod_d / 2 - outer_t ) + tube_t )"
equation "d565 = abs(( ( -close_gap / 2 ) - tube_w ) + tube_t)"
equation "d566 = abs(( pod_d / 2 - outer_t ) + tube_t)"
equation "d567 = ( ( panel_z0 + back_ph ) - top_h ) - ( ( panel_z0 ) + tube_w )"
equation "d569 = ( panel_z0 ) + tube_w"
equation "d571 = ( ( -close_gap / 2 - half_fw ) + stile_pitch + tube_w ) - ( ( -close_gap / 2 - half_fw ) + stile_pitch )"
equation "d572 = ( pod_d / 2 - skin_t - bond_t ) - ( pod_d / 2 - outer_t )"
equation "d573 = abs(( -close_gap / 2 - half_fw ) + stile_pitch)"
equation "d574 = abs(pod_d / 2 - outer_t)"
equation "d575 = ( ( panel_z0 + back_ph ) - top_h ) - ( ( panel_z0 ) + tube_w )"
equation "d577 = ( panel_z0 ) + tube_w"
equation "d579 = ( ( ( -close_gap / 2 - half_fw ) + stile_pitch + tube_w ) - stud_t ) - ( ( ( -close_gap / 2 - half_fw ) + stile_pitch ) + stud_t )"
equation "d580 = ( ( pod_d / 2 - skin_t - bond_t ) - stud_t ) - ( ( pod_d / 2 - outer_t ) + stud_t )"
equation "d581 = abs(( ( -close_gap / 2 - half_fw ) + stile_pitch ) + stud_t)"
equation "d582 = abs(( pod_d / 2 - outer_t ) + stud_t)"
equation "d583 = ( ( panel_z0 + back_ph ) - top_h ) - ( ( panel_z0 ) + tube_w )"
equation "d585 = stile_n_mid"
equation "d587 = stile_pitch"
equation "d589 = panel_z0"
equation "d591 = abs(( -close_gap / 2 - half_fw ) + bolt_edge)"
equation "d592 = abs(pod_d / 2 - skin_t - bond_t - tube_d / 2)"
equation "d593 = tube_t"
equation "d594 = bolt_d"
equation "d596 = ( panel_z0 ) + tube_w"
equation "d598 = abs(( -close_gap / 2 - half_fw ) + bolt_edge)"
equation "d599 = abs(pod_d / 2 - skin_t - bond_t - tube_d / 2)"
equation "d600 = tube_t"
equation "d601 = access_d"
equation "d603 = n_len_bolt"
equation "d605 = len_bolt_pitch"
equation "d607 = panel_z0"
equation "d609 = abs(( -close_gap / 2 ) - 1 * spigot_edge)"
equation "d610 = abs(pod_d / 2 - skin_t - bond_t - tube_d / 2)"
equation "d611 = tube_t"
equation "d612 = spigot_d"
equation "d614 = panel_z0"
equation "d616 = ( ( ( -close_gap / 2 - half_fw ) + 1 * spigot_edge ) + ( spigot_slot - spigot_d ) / 2 ) - ( ( ( -close_gap / 2 - half_fw ) + 1 * spigot_edge ) - ( spigot_slot - spigot_d ) / 2 )"
equation "d617 = ( ( pod_d / 2 - skin_t - bond_t - tube_d / 2 ) + spigot_d / 2 ) - ( ( pod_d / 2 - skin_t - bond_t - tube_d / 2 ) - spigot_d / 2 )"
equation "d618 = abs(( ( -close_gap / 2 - half_fw ) + 1 * spigot_edge ) - ( spigot_slot - spigot_d ) / 2)"
equation "d619 = abs(( pod_d / 2 - skin_t - bond_t - tube_d / 2 ) - spigot_d / 2)"
equation "d620 = ( ( panel_z0 ) + tube_t ) - ( panel_z0 )"
equation "d622 = panel_z0"
equation "d624 = abs(( ( -close_gap / 2 - half_fw ) + 1 * spigot_edge ) - ( spigot_slot - spigot_d ) / 2)"
equation "d625 = abs(pod_d / 2 - skin_t - bond_t - tube_d / 2)"
equation "d626 = tube_t"
equation "d627 = spigot_d"
equation "d629 = panel_z0"
equation "d631 = abs(( ( -close_gap / 2 - half_fw ) + 1 * spigot_edge ) + ( spigot_slot - spigot_d ) / 2)"
equation "d632 = abs(pod_d / 2 - skin_t - bond_t - tube_d / 2)"
equation "d633 = tube_t"
equation "d634 = spigot_d"
equation "d636 = panel_z0 + back_ph"
equation "d638 = abs(( -close_gap / 2 - half_fw ) + bolt_edge)"
equation "d639 = abs(pod_d / 2 - skin_t - bond_t - tube_d / 2)"
equation "d640 = tube_t"
equation "d641 = rivnut_d"
equation "d643 = n_len_bolt"
equation "d645 = len_bolt_pitch"
equation "d647 = panel_z0 + back_ph"
equation "d649 = abs(( -close_gap / 2 - half_fw ) + spigot_edge)"
equation "d650 = abs(pod_d / 2 - skin_t - bond_t - tube_d / 2)"
equation "d651 = tube_t"
equation "d652 = rivnut_d"
equation "d654 = panel_z0 + back_ph"
equation "d656 = abs(( -close_gap / 2 ) - spigot_edge)"
equation "d657 = abs(pod_d / 2 - skin_t - bond_t - tube_d / 2)"
equation "d658 = tube_t"
equation "d659 = rivnut_d"
equation "d661 = -close_gap / 2 - half_fw"
equation "d663 = abs(bolt_line_y)"
equation "d664 = abs(( panel_z0 ) + bolt_edge)"
equation "d665 = tube_t"
equation "d666 = bolt_d"
equation "d668 = ( -close_gap / 2 - half_fw ) + 1 * tube_w"
equation "d670 = abs(bolt_line_y)"
equation "d671 = abs(( panel_z0 ) + bolt_edge)"
equation "d672 = tube_t"
equation "d673 = access_d"
equation "d675 = n_side_jnt"
equation "d677 = side_jnt_pitch"
equation "d679 = -close_gap / 2"
equation "d681 = abs(pod_d / 2 - skin_t - bond_t - tube_d / 2)"
equation "d682 = abs(( panel_z0 ) + bolt_edge)"
equation "d683 = tube_t"
equation "d684 = bolt_d"
equation "d686 = n_side_jnt"
equation "d688 = side_jnt_pitch"
equation "d690 = lead_in"
named bodies: "RAIL - BOTTOM", "RAIL - TOP", "STILE - OUTER", "STILE - CENTRE", "STILE - MID 1", "STILE - MID 2"
